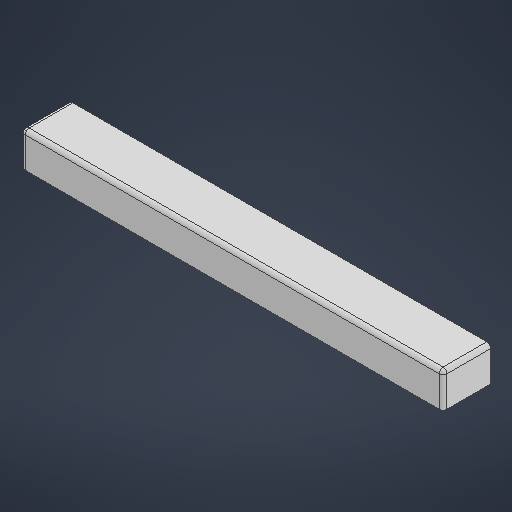
# Autodesk Inventor part: lock_bar
Saved by Autodesk Inventor 2027 (Build 310192060, 192F)
## iProperties
Created: 2026-10-18
Part Number: lock_bar
Material: Générique
Document SubType Name: Modeling
Designer: strei
Density: 1 g/cm^3
Appearance: Par défaut
Author: strei
Autodesk Inventor part; units mm, degrees
ref_plane "YZ Plane" through (0, 0, 0) normal (1, 0, 0) x (0, 1, 0)
ref_plane "XZ Plane" through (0, 0, 0) normal (0, 1, 0) x (-1, 0, 0)
ref_plane "XY Plane" through (0, 0, 0) normal (0, 0, 1) x (1, 0, 0)
sketch "Esquisse1" plane through (0, 0, 0) normal (0, 1, 0) x (-1, 0, 0)
  line L0 (320, -35) -> (-320, -35)
  line L1 (-320, -35) -> (-320, 35)
  line L2 (-320, 35) -> (320, 35)
  line L3 (320, 35) -> (320, -35)
  line L4 (320, -35) -> (-320, 35) construction
  line L5 (-320, -35) -> (320, 35) construction
  point P0 (0, 0)
  dimension "d0" = 640
  dimension "d1" = 70
  constraints: 12 end point, 2 midpoint, 2 parallel, 1 horizontal, 1 perpendicular
  measures "d0" distance of L1.end L2.end
  measures "d1" distance of L0.end L1.end
extrude "Extrusion1" add sketch "Esquisse1" along normal blind 50
shell "Coque1" thickness 3 outward yes removed faces 2 at (106.6667, 16.6667, -35) at (-106.6667, 0, -11.6667)
fillet "Congé1" radius 6 5 edges at (-323, 53, 1.5) (-323, 26.5, 38) (0, 53, 38) (323, 53, 1.5) (323, 26.5, 38)
